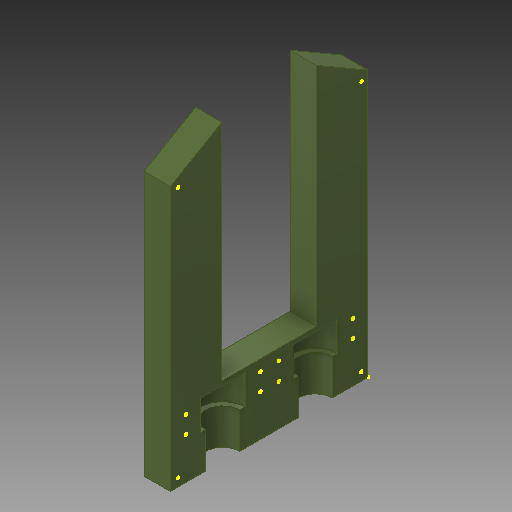
# Autodesk Inventor part: Floating Bed
Saved by Autodesk Inventor 2019 (Build 230136000, 136)
## iProperties
Created: 2019-03-21
Part Number: Floating Bed
Material: Generic
Document SubType Name: Modeling
Designer: Dell
Density: 1 g/cm^3
Appearance: Dark Olive
Author: Dell
Autodesk Inventor part; units mm, degrees
ref_plane "YZ Plane" through (0, 0, 0) normal (1, 0, 0) x (0, 1, 0)
ref_plane "XZ Plane" through (0, 0, 0) normal (0, 1, 0) x (-1, 0, 0)
ref_plane "XY Plane" through (0, 0, 0) normal (0, 0, 1) x (1, 0, 0)
sketch "Sketch1" plane through (0, 0, 0) normal (1, 0, 0) x (0, 1, 0)
  line L0 (80, 58.9167) -> (338.775, 58.9167)
  line L1 (80, 167.0833) -> (80, 58.9167)
  line L2 (336.4656, 167.0833) -> (80, 167.0833)
  line L3 (302.45, 226) -> (336.4656, 167.0833)
  line L4 (0, 226) -> (302.45, 226)
  line L5 (0, 226) -> (0, 0)
  line L6 (304.7594, 0) -> (0, 0)
  line L7 (304.7594, 0) -> (338.775, 58.9167)
  point P0 (0, 113)
  constraints: 16 end point
extrude "Extrusion1" add sketch "Sketch1" along normal blind 30
sketch "Sketch3" plane through (0, 0, 0) normal (0, -1, 0) x (1, 0, 0)
  circle A0 centre (30, 166) radius 19.5 projected
  circle A1 centre (30, 60) radius 19.5 projected
  point P0 (0, 0)
extrude "Extrusion2" cut sketch "Sketch3" against normal blind 41
sketch "Sketch4" plane through (0, 41, 0) normal (0, -1, 0) x (1, 0, 0)
  circle A0 centre (30, 166) radius 25.5 projected
  circle A1 centre (30, 60) radius 25.5 projected
  point P0 (0, 0)
extrude "Extrusion3" cut sketch "Sketch4" against normal blind 34
sketch "Sketch5" plane through (30, 0, 0) normal (1, 0, 0) x (0, 0, -1)
  ellipse E0 centre (-208.5211, 48) end of major axis (-208.5211, 46.5) minor radius 1.4999 projected
  ellipse E1 centre (-208.5211, 68) end of major axis (-208.5211, 66.5) minor radius 1.4999 projected
  ellipse E2 centre (-123.5248, 48) end of major axis (-123.5248, 46.5) minor radius 1.4999 projected
  ellipse E3 centre (-123.5248, 68) end of major axis (-123.5248, 66.5) minor radius 1.4999 projected
  ellipse E4 centre (-102.4606, 48) end of major axis (-102.4606, 46.5) minor radius 1.4999 projected
  ellipse E5 centre (-102.4606, 68) end of major axis (-102.4606, 66.5) minor radius 1.4999 projected
  ellipse E6 centre (-17.4687, 48) end of major axis (-17.4687, 46.5) minor radius 1.4999 projected
  ellipse E7 centre (-17.4687, 68) end of major axis (-17.4687, 66.5) minor radius 1.4999 projected
  point P0 (0, 0)
  constraints: 8 other
sketch "Sketch6" plane through (30, 0, 0) normal (1, 0, 0) x (0, 0, -1)
  circle A0 centre (-217.9704, 297.7535) radius 1.5 projected
  circle A1 centre (-218.1266, 9.9435) radius 1.5 projected
  circle A2 centre (-7.9983, 9.9012) radius 1.5 projected
  circle A3 centre (-7.8606, 297.8416) radius 1.5 projected
  point P0 (0, 0)
sketch "Sketch7" plane through (30, 0, 0) normal (1, 0, 0) x (0, 0, -1)
  point P0 (0, 0)
  point P1 (-7.8989, 9.8938)
  point P2 (-218.0482, 10.1478)
  point P3 (-218.2874, 297.6442)
  point P4 (-8.5245, 297.8695)
hole "Hole1" at (30, 9.8938, 7.8989) at (30, 10.1478, 218.0482) at (30, 297.6442, 218.2874) at (30, 297.8695, 8.5245) direction (-1, 0, 0) diameter 3 depth 10 tip angle 118
sketch "Sketch9" plane through (30, 0, 0) normal (1, 0, 0) x (0, 0, -1)
  ellipse E0 centre (-102.4305, 68) end of major axis (-102.4305, 70.5) minor radius 2.4998 projected
  ellipse E1 centre (-102.4305, 48) end of major axis (-102.4305, 50.5) minor radius 2.4998 projected
  ellipse E2 centre (-17.4386, 68) end of major axis (-17.4386, 70.5) minor radius 2.4998 projected
  ellipse E3 centre (-17.4386, 48) end of major axis (-17.4386, 50.5) minor radius 2.4998 projected
  circle A0 centre (-123.5002, 48) radius 2.5 projected
  circle A1 centre (-208.4998, 48) radius 2.5 projected
  circle A2 centre (-208.4998, 68) radius 2.5 projected
  circle A3 centre (-123.5002, 68) radius 2.5 projected
  constraints: 4 other
hole "Hole3" at (30, 68, 102.4305) at (30, 48, 102.4305) at (30, 68, 17.4386) at (30, 48, 17.4386) direction (-1, 0, 0) diameter 5 end through all
body "Solid1"
